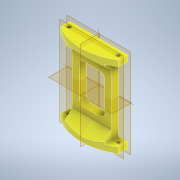
# Autodesk Inventor part: Lateral Support
Saved by Autodesk Inventor 2021 (Build 250183000, 183)
## iProperties
Created: 2026-04-22
Part Number: Lateral Support
Material: Generic
Document SubType Name: Modeling
Designer: Admin
Density: 1 g/cm^3
Appearance: Yellow
Author: Admin
Autodesk Inventor part; units mm, degrees
sketch "Sketch1" plane through (0, 0, 0) normal (0, 1, 0) x (-1, 0, 0)
  line L0 (-25, 0) -> (25, 0)
  line L1 (0, -41.8887) -> (0, 24.6113) projected
  line L2 (25, 0) -> (25, 8)
  line L3 (-25, 0) -> (-25, 8)
  arc A0 (25, 8) -> (-25, 8) centre (0, -32.3887) ccw
  line L4 (-35, 0) -> (35, 0) projected
  point P0 (0, 0)
  point P1 (0, 0)
  dimension "d0" = 47.5
  dimension "d1" = 8
  dimension "d2" = 50
  constraints: 6 end point, 2 midpoint, 2 point on circle, 2 vertical, 1 centre point, 1 horizontal, 1 parallel, 1 point on line
  measures "d0" radius of A0
  measures "d1" distance of L0.end L2.end
  measures "d2" distance of L0.start L0.end
extrude "Extrusion1" add sketch "Sketch1" along normal mid plane 70
sketch "Sketch2" plane through (0, 0, 0) normal (0, 0, 1) x (1, 0, 0)
  line L0 (-33, -30) -> (-17, -30)
  line L1 (-17, -30) -> (-17, 30)
  line L2 (-17, 30) -> (-33, 30)
  line L3 (-33, 30) -> (-33, -30)
  line L4 (-25, -35) -> (-25, 35) projected
  line L5 (-33, -30) -> (-17, 30) construction
  line L6 (-17, -30) -> (-33, 30) construction
  line L7 (25, 35) -> (-25, 35) projected
  point P0 (0, 0)
  point P1 (-25, 0)
  dimension "d6" = 8
  dimension "d8" = 5
  constraints: 12 end point, 3 midpoint, 2 parallel, 1 horizontal, 1 perpendicular
  measures "d6" distance between parallel lines of L1 L4
  measures "d8" distance between parallel lines of L7 L2
extrude "Extrusion2" cut sketch "Sketch2" along normal blind 60
sketch "Sketch4" plane through (0, 35, 0) normal (0, 1, 0) x (1, 0, 0)
  line L0 (35, 0) -> (-35, 0) projected
  line L1 (-25, 0) -> (-25, -8) projected
  circle A0 centre (0, 32.3887) radius 42.5
  arc A1 (-25, -8) -> (25, -8) centre (0, 32.3887) ccw projected
  line L2 (-21.25, -4.4173) -> (0, 32.3887)
  line L3 (0, 92.8887) -> (0, -33.1113) projected
  point P0 (0, 0)
  dimension "d20" = 85
  dimension "d21" = 30
  constraints: 2 end point, 4 other
  measures "d21" angle of L3 L2
hole "Hole1" at (-21.25, 35, 4.4173) direction (0, -1, 0) diameter 3.4 depth 80 clearance for "Countersunk Flat Head Screw ISO 2009/7046" size "M3" standard "ISO"
mirror "Mirror1" about plane through (0, 0, 0) normal (1, 0, 0) of "Hole1", "Extrusion2"
ref_plane "Work Plane1" through (0, 0, 6) normal (0, 0, 1) x (1, 0, 0)
sketch "Sketch5" plane through (0, 0, 6) normal (0, 0, 1) x (1, 0, 0)
  line L0 (-23.9632, -23) -> (23.9632, -23)
  line L1 (23.9632, -23) -> (23.9632, 23)
  line L2 (23.9632, 23) -> (-23.9632, 23)
  line L3 (-23.9632, 23) -> (-23.9632, -23)
  line L4 (-23.9632, -23) -> (23.9632, 23) construction
  line L5 (23.9632, -23) -> (-23.9632, 23) construction
  line L6 (-17, 30) -> (-25, 30) projected
  point P0 (0, 0)
  dimension "d23" = 7
  constraints: 12 end point, 2 midpoint, 2 parallel, 1 horizontal, 1 perpendicular
  measures "d23" distance between parallel lines of L6 L2
extrude "Extrusion3" cut sketch "Sketch5" along normal blind 10
draft "FaceDraft1" angle 40 pull direction (0, 0, 1) faces at (0, -23, 9.0371) fixed edges at (0, -23, 6)
draft "FaceDraft2" angle 40 pull direction (0, 0, 1) faces at (0, 23, 9.0371) fixed edges at (0, 23, 6)
sketch "Sketch6" plane through (0, 0, 6) normal (0, 0, 1) x (1, 0, 0)
  line L0 (-11, -17) -> (11, -17)
  line L1 (11, -17) -> (11, 17)
  line L2 (11, 17) -> (-11, 17)
  line L3 (-11, 17) -> (-11, -17)
  line L4 (-11, -17) -> (11, 17) construction
  line L5 (11, -17) -> (-11, 17) construction
  line L6 (-17, -23) -> (-17, 23) projected
  line L7 (17, 23) -> (-17, 23) projected
  line L8 (0, 49) -> (0, -49) projected
  line L9 (-35, 0) -> (35, 0) projected
  point P0 (0, 0)
  point P1 (0, 0)
  point P2 (0, 0)
  dimension "d29" = 6
  dimension "d30" = 6
  constraints: 12 end point, 6 midpoint, 2 parallel, 1 horizontal, 1 perpendicular
  measures "d29" distance between parallel lines of L6 L3
  measures "d30" distance between parallel lines of L7 L2
extrude "Extrusion4" cut sketch "Sketch6" against normal blind 10 contours L3 L9 L8 L0 | L8 L9 L1 L0 | L3 L2 L8 L9 | L8 L2 L1 L9
fillet "Fillet2" radius 4 4 edges at (-11, 17, 3) (11, 17, 3) (-11, -17, 3) (11, -17, 3)
body "Solid1"
